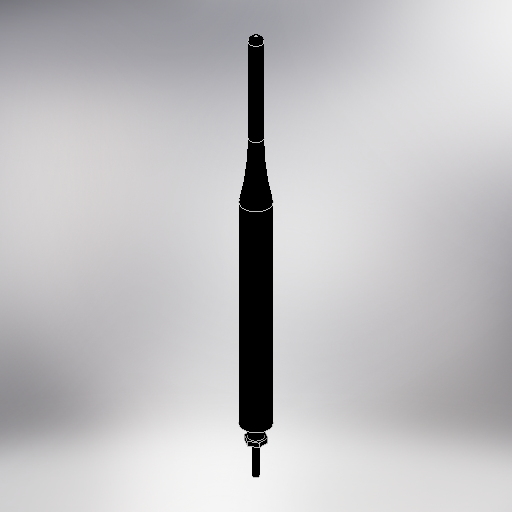
# Autodesk Inventor part: antenna
Saved by Autodesk Inventor 2027 (Build 310192060, 192F)
## iProperties
Created: 2026-08-12
Part Number: antenna
Material: Generic
Document SubType Name: Modeling
Designer: Aiden
Density: 1 g/cm^3
Appearance: Anodized - Black
Author: Aiden
Autodesk Inventor part; units mm, degrees
ref_plane "YZ Plane" through (0, 0, 0) normal (1, 0, 0) x (0, 1, 0)
ref_plane "XZ Plane" through (0, 0, 0) normal (0, 1, 0) x (-1, 0, 0)
ref_plane "XY Plane" through (0, 0, 0) normal (0, 0, 1) x (1, 0, 0)
sketch "Sketch1" plane through (0, 0, 0) normal (0, 1, 0) x (-1, 0, 0)
  line L0 (0, 4.6188) -> (4, 2.3094)
  line L1 (4, 2.3094) -> (4, -2.3094)
  line L2 (4, -2.3094) -> (0, -4.6188)
  line L3 (0, -4.6188) -> (-4, -2.3094)
  line L4 (-4, -2.3094) -> (-4, 2.3094)
  line L5 (-4, 2.3094) -> (0, 4.6188)
  line L6 (0, 4.6188) -> (0, -4.6188) construction
  point P0 (0, 0)
  point P1 (0, 0)
  dimension "d0" = 120
  dimension "d10" = 8
  constraints: 14 end point, 5 equal length, 2 vertical, 1 coincident, 1 midpoint, 1 parallel
  measures "d0" angle of L1 L0
  measures "d10" distance between parallel lines of L4 L1
extrude "Extrusion1" add sketch "Sketch1" along normal blind 2.1717
sketch "Sketch7" plane through (0, 0, 0) normal (0, -1, 0) x (1, 0, 0)
  circle A0 centre (0, 0) radius 1.444
  constraints: 1 centre point, 1 coincident
extrude "Extrusion7" add sketch "Sketch7" along normal blind 16
sketch "Sketch8" plane through (0, 2.1717, 0) normal (0, 1, 0) x (1, 0, 0)
  circle A0 centre (0, 0) radius 3.2
  dimension "d22" = 6.4
  constraints: 1 centre point, 1 coincident
  measures "d22" diameter of A0
extrude "Extrusion8" add sketch "Sketch8" along normal blind 6.08
sketch "Sketch9" plane through (0, 8.2517, 0) normal (0, 1, 0) x (1, 0, 0)
  circle A0 centre (0, 0) radius 6.5
  dimension "d25" = 13
  constraints: 1 centre point, 1 coincident
  measures "d25" diameter of A0
extrude "Extrusion9" add sketch "Sketch9" along normal blind 101.6
sketch "Sketch10" plane through (0, 109.8517, 0) normal (0, 1, 0) x (1, 0, 0)
  circle A0 centre (0, 0) radius 1.444 projected
  circle A1 centre (0, 0) radius 3.0543
  dimension "d28" = 6.1087
  constraints: 1 centre point, 1 coincident
  measures "d28" diameter of A1
extrude "Extrusion10" add sketch "Sketch10" along normal blind 76.2 contours A0 | A1
fillet "Fillet3" radius 127 1 edges at (-3.0543, 109.8517, 0)
fillet "Fillet4" radius 2.54 1 edges at (-3.0543, 186.0517, 0)
body "Solid1"
